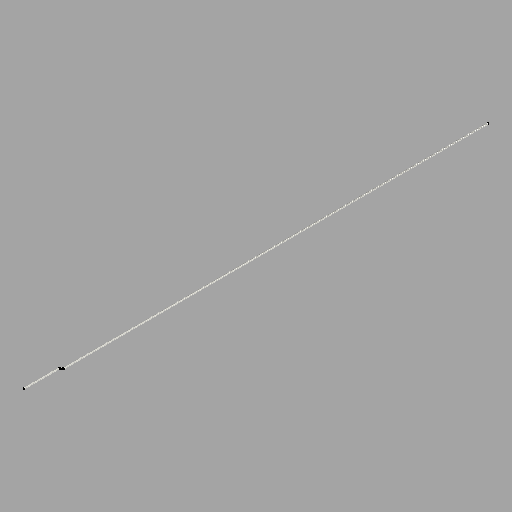
# Autodesk Inventor part: Cell_Ribbon_End
Saved by Autodesk Inventor 2026.2 (Build 302298000, 298)
## iProperties
Created: 2026-11-08
Part Number: Cell_Ribbon_End
Material: Generic
Document SubType Name: Modeling
Designer: Jacob
Density: 1 g/cm^3
Appearance: Default
Author: Jacob
Autodesk Inventor part; units mm, degrees
ref_plane "YZ Plane" through (0, 0, 0) normal (1, 0, 0) x (0, 1, 0)
ref_plane "XZ Plane" through (0, 0, 0) normal (0, 1, 0) x (-1, 0, 0)
sketch "Sketch1" plane through (0, 0, 0) normal (1, 0, 0) x (0, 1, 0)
  line L0 (-0.15, -83.17) -> (-0.15, 0.2034)
  line L1 (-0.0529, 0.4995) -> (0.2179, 0.8679)
  line L2 (0.315, 1.164) -> (0.315, 8)
  arc A0 (-0.0529, 0.4995) -> (-0.15, 0.2034) centre (0.35, 0.2034) ccw
  arc A1 (0.2179, 0.8679) -> (0.315, 1.164) centre (-0.185, 1.164) ccw
  point P0 (0, 0)
  dimension "d0" = 0.15
  dimension "d1" = 0.315
  dimension "d2" = 83.17
  dimension "d3" = 8
  constraints: 6 end point, 4 point on circle, 4 tangent, 2 centre point, 2 vertical
  measures "d0" horizontal distance of point (0, 0) L0.start
  measures "d1" horizontal distance of point (0, 0) L2.end
  measures "d2" distance of point (0, 0) L0.start
  measures "d3" vertical distance of point (0, 0) L2.end
ref_plane "Work Plane1" through (0, -0.15, -83.17) normal (0, 0, 1) x (1, 0, 0)
sketch "Sketch2" plane through (0, -0.15, -83.17) normal (0, 0, 1) x (1, 0, 0)
  circle A0 centre (0, 0) radius 0.135
  dimension "d4" = 0.27
  constraints: 1 centre point
  measures "d4" diameter of A0
sweep "Copper_Core_Sweep" add profiles "Sketch2" path "Sketch1" path curves L0 A0 L1 A1 L2
sketch "Sketch3" plane through (0, -0.15, -83.17) normal (0, 0, 1) x (1, 0, 0)
  circle A0 centre (0, 0) radius 0.135
  circle A1 centre (0, 0) radius 0.15
  dimension "d7" = 0.27
  dimension "d8" = 0.3
  constraints: 2 centre point
  measures "d7" diameter of A0
  measures "d8" diameter of A1
sweep "SnPb_Coating_Sweep" add profiles "Sketch3" path "Sketch1" separate body path curves L0 A0 L1 A1 L2 contours A0 | A1
equation "\"d0\" = 0.5 * Wire_OD"
equation "\"d1\" = Cell_Thickness + 0.5 * Wire_OD"
equation "\"d2\" = Ribbon_Pad_Length"
equation "\"d3\" = Ribbon_Overhang"
equation "\"d4\" = Cu_Dia"
equation "\"d7\" = Cu_Dia"
equation "\"d8\" = Wire_OD"
equation "\"Cu_Dia\" = 0.27"
equation "\"Wire_OD\" = 0.3"
equation "\"Cell_Thickness\" = 0.165"
equation "\"Ribbon_Pad_Length\" = 83.17"
equation "\"Ribbon_Overhang\" = 8"
